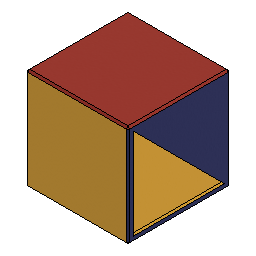
color-cube (Autodesk Fusion 360 design; units mm, degrees)
Autodesk Fusion 360 part; units mm, degrees
box "BoxPrimitive1" add length 27.5 width 27.5 height 27.5 placed x (0, 1, 0) y (-1, 0, 0) z (0, 0, 1) at (27.5, 0, 0)
sketch "Sketch2" plane through (27.5, 0, 0) normal (1, 0, 0) x (0, 1, 0)
  line L0 (0, 27.5) -> (0, 0)
  line L1 (0, 0) -> (27.5, 0)
  line L2 (27.5, 0) -> (27.5, 27.5)
  line L3 (27.5, 27.5) -> (0, 27.5)
  line L4 (0, 0) -> (27.5, 27.5)
  line L5 (1.5, 1.5) -> (26, 1.5)
  line L6 (26, 1.5) -> (26, 26)
  line L7 (26, 26) -> (1.5, 26)
  line L8 (1.5, 26) -> (1.5, 1.5)
  dimension "d8" = -1.5
  constraint coincident L0.end L1.start
  constraint coincident L2.end L3.start
extrude "Extrude1" cut sketch "Sketch2" against normal blind 0.8 contours L4 L7 L8
sketch "Sketch3" plane through (0, 0, 0) normal (-1, 0, 0) x (0, -1, 0)
  line L0 (-27.5, 27.5) -> (-27.5, 0)
  line L1 (-27.5, 0) -> (0, 0)
  line L2 (0, 0) -> (0, 27.5)
  line L3 (0, 27.5) -> (-27.5, 27.5)
  line L4 (-1.5, 26) -> (-1.5, 1.5)
  line L5 (-1.5, 1.5) -> (-26, 26)
  line L6 (-26, 26) -> (-1.5, 26)
extrude "Extrude2" cut sketch "Sketch3" against normal blind 0.8 contours L4 L5 L6
move_body "Move1" bodies 1 to x (-1, 0, 0) y (0, 1, 0) z (0, 0, -1) at (27.5, 0, 27.5)
chamfer "Chamfer1" distance 0.5 angle 45 12 edges at (0, 13.75, 0) (13.75, 27.5, 0) (27.5, 13.75, 0) (13.75, 0, 0) (0, 0, 13.75) (0, 27.5, 13.75) (27.5, 0, 13.75) (27.5, 27.5, 13.75) (13.75, 0, 27.5) (0, 13.75, 27.5) (13.75, 27.5, 27.5) (27.5, 13.75, 27.5)
scale "Scale1" factor 0.98 about (0, 0, 0) bodies 1
named bodies: "Single Color Cube"
